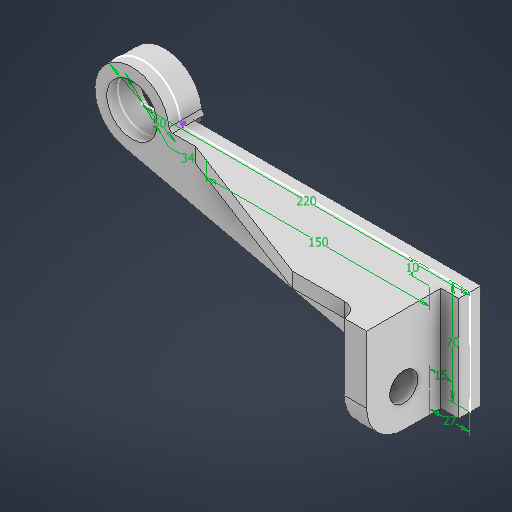
# Autodesk Inventor part: Peça7
Saved by Autodesk Inventor 2026.2 (Build 302298000, 298)
## iProperties
Created: 2026-08-07
Part Number: Peça7
Material: Genérico
Document SubType Name: Modeling
Designer: IFSP
Density: 1 g/cm^3
Appearance: Padrão
Author: IFSP
Autodesk Inventor part; units mm, degrees
ref_plane "YZ Plane" through (0, 0, 0) normal (1, 0, 0) x (0, 1, 0)
ref_plane "XZ Plane" through (0, 0, 0) normal (0, 1, 0) x (-1, 0, 0)
ref_plane "XY Plane" through (0, 0, 0) normal (0, 0, 1) x (1, 0, 0)
sketch "Esboço1" plane through (0, 0, 0) normal (0, 0, 1) x (1, 0, 0)
  line L0 (0, 0) -> (-220, 0)
  circle A0 centre (-220, 0) radius 17
  arc A1 (-195.1034, 2.2719) -> (-195, 0) centre (-220, 0) ccw
  line L1 (0, 0) -> (0, -70)
  line L2 (0, -70) -> (-27, -70)
  line L3 (-27, -70) -> (-225.5987, -24.365)
  arc A2 (-195.1034, 2.2719) -> (-192.6821, 0) centre (-192.6138, 2.4991) ccw
  line L4 (-27, -70) -> (-27, 0)
  line L5 (-27, 0) -> (-27, -10)
  line L6 (-27, -10) -> (-177, -10)
  line L7 (-177, -10) -> (-177, 0)
  line L8 (-27, -70) -> (-12, -70)
  line L9 (-12, -70) -> (-12, 0)
  dimension "d0" = 220
  dimension "d1" = 34
  dimension "d2" = 50
  dimension "d3" = 70
  dimension "d4" = 27
  dimension "d13" = 10
  dimension "d14" = 150
  dimension "d15" = 15
  constraints: 20 end point, 7 point on line, 5 point on circle, 4 perpendicular, 3 centre point, 2 coincident, 2 horizontal, 1 tangent, 1 vertical
  measures "d0" distance of L0.start L0.end
  measures "d1" diameter of A0
  measures "d2" diameter of A1
  measures "d3" distance of L0.start L1.end
  measures "d4" distance of L1.end L2.end
  measures "d13" distance of L4.end L5.end
  measures "d14" distance of L5.end L6.end
  measures "d15" distance of L2.end L8.end
extrude "Extrusão1" add sketch "Esboço1" along normal mid plane 15
extrude "Extrusão2" add sketch "Esboço1" against normal blind 14.5 contours L0 A1 A2
extrude "Extrusão3" add sketch "Esboço1" along normal blind 57.5 contours L9 L2 L4 L0 | L4 L6 L7 L0
sketch "Esboço2" plane through (-177, -10, 7.5) normal (0, -1, 0) x (1, 0, 0)
  line L0 (0, 50) -> (150, 50) projected
  line L1 (150, 50) -> (105, 50)
  line L2 (150, 0) -> (0, 0) projected
  line L3 (150, 0) -> (150, 40)
  line L4 (150, 0) -> (150, 50) projected
  line L5 (150, 40) -> (150, -5)
  line L6 (150, 0) -> (150, 40)
  line L7 (150, 40) -> (105, 40)
  line L8 (105, 40) -> (0, 0)
  line L9 (0, 0) -> (0, 50)
  line L10 (150, 50) -> (150, 40)
  point P0 (177, -7.5)
  dimension "d21" = 40
  dimension "d22" = 45
  constraints: 16 end point, 3 point on line, 2 collinear, 2 perpendicular
  measures "d21" distance of L2.start L3.end
  measures "d22" distance of L3.end L7.end
extrude "Extrusão4" cut sketch "Esboço2" against normal blind 57.5 contours L0 L4 L7 L8 L9
fillet "Arredondamento da face1" radius 10 1 edges at (-27, -5, 47.5)
sketch "Esboço3" plane through (-27, -70, 7.5) normal (-1, 0, 0) x (0, 0, 1)
  circle A0 centre (25, 25) radius 9.5
  line L0 (50, 60) -> (50, 0) projected
  line L1 (0, 0) -> (50, 0) projected
  circle A1 centre (25, 25) radius 25
  line L2 (50, 25) -> (50, 0)
  point P0 (-7.5, 70)
  point P1 (25, 0)
  dimension "d29" = 50
  dimension "d26" = 19
  dimension "d27" = 25
  dimension "d28" = 25
  constraints: 2 end point, 1 centre point, 1 coincident, 1 collinear, 1 point on line, 3 other
  measures "d26" diameter of A0
  measures "d27" distance from line of L0 A0.centre
  measures "d28" distance from line of A0.centre L1
extrude "Extrusão5" cut sketch "Esboço3" against normal blind 57.5 contours A0 | L0 L1 A1
